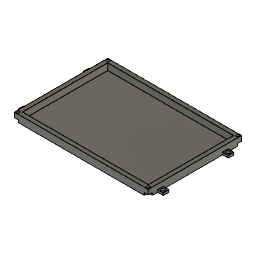
Mainboard frame (Autodesk Fusion 360 design; units mm, degrees)
Autodesk Fusion 360 part; units mm, degrees
sketch "Sketch1" plane through (0, 0, 0) normal (0, 0, 1) x (1, 0, 0)
  line L0 (0, 0) -> (165, 0)
  line L1 (165, 0) -> (165, 115)
  line L2 (165, 115) -> (0, 115)
  line L3 (0, 115) -> (0, 0)
  dimension "d1" = 165
  dimension "d2" = 115
  constraint horizontal L0
  constraint vertical L1
  constraint horizontal L2
  constraint vertical L3
  constraint coincident L0.start L3.end
  measures "d1" distance of L0.start L0.end
  measures "d2" distance of L0.start L2.end
extrude "Extrude1" add sketch "Sketch1" along normal blind 0.8 makes body 1
sketch "Sketch2" plane through (0, 0, 0.8) normal (0, 0, 1) x (-1, 0, 0)
  line L0 (0, -115) -> (0, 0)
  line L1 (0, 0) -> (-165, 0)
  line L2 (-165, 0) -> (-165, -115)
  line L3 (-165, -115) -> (0, -115)
  line L4 (-160, -5) -> (-5, -5)
  line L5 (-5, -5) -> (-5, -110)
  line L6 (-5, -110) -> (-160, -110)
  line L7 (-160, -110) -> (-160, -5)
  line L8 (-160, -5) -> (-5, -110) construction
  line L9 (-5, -5) -> (-160, -110) construction
  point P0 (-82.5, -57.5)
  dimension "d5" = 155
  dimension "d6" = 105
  constraint horizontal L4
  constraint perpendicular L4 L5
  constraint parallel L4 L6
  constraint parallel L5 L7
  constraint coincident L8 P0
  constraint coincident L9 P0
  measures "d5" distance of L5.end L6.end
  measures "d6" distance of L4.end L5.end
extrude "Extrude2" add sketch "Sketch2" along normal blind 0.2 bodies 1
sketch "Sketch3" plane through (0, 0, 1) normal (0, 0, 1) x (-1, 0, 0)
  line L0 (-5, -110) -> (-160, -110)
  line L1 (-160, -110) -> (-160, -5)
  line L2 (-160, -5) -> (-5, -5)
  line L3 (-5, -5) -> (-5, -110)
  line L4 (-165, -115) -> (0, -115)
  line L5 (0, -115) -> (0, 0)
  line L6 (0, 0) -> (-165, 0)
  line L7 (-165, 0) -> (-165, -115)
  circle A0 centre (-2.5, -2.5) radius 1.7
  circle A1 centre (-162.5, -112.5) radius 1.7
  circle A2 centre (-2.5, -112.5) radius 1.7
  circle A3 centre (-162.5, -2.5) radius 1.7
  dimension "d9" = 3.4
  dimension "d10" = 3.4
  dimension "d11" = 3.4
  dimension "d12" = 3.4
  measures "d9" diameter of A0
  measures "d10" diameter of A1
  measures "d11" diameter of A2
  measures "d12" diameter of A3
extrude "Extrude3" cut sketch "Sketch3" against normal blind 367 contours A0 | A1 | A2 | A3 bodies 1
sketch "Sketch4" plane through (0, 0, 0) normal (0, 0, -1) x (1, 0, 0)
  circle A0 centre (162.5, -112.5) radius 1.7
  circle A1 centre (2.5, -2.5) radius 1.7
  circle A2 centre (2.5, -112.5) radius 1.7
  circle A3 centre (162.5, -2.5) radius 1.7
  line L0 (0, 0) -> (0, -115)
  line L1 (0, -115) -> (165, -115)
  line L2 (165, -115) -> (165, 0)
  line L3 (165, 0) -> (0, 0)
sketch "Sketch5" plane through (0, 0, 0) normal (0, 0, -1) x (1, 0, 0)
extrude "Extrude4" add 1 faces at (56.6478, 111.9912, 1) along direction (0, 0, 1) blind 8 on bodies 1 bodies 1
sketch "Sketch6" plane through (0, 0, 0) normal (0, 0, -1) x (1, 0, 0)
  line L0 (5, -5) -> (0, -5)
  line L1 (0, -5) -> (0, 0)
  line L2 (0, 0) -> (5, 0)
  line L3 (5, 0) -> (5, -5)
  line L4 (5, -110) -> (0, -110)
  line L5 (0, -110) -> (0, -115)
  line L6 (0, -115) -> (5, -115)
  line L7 (5, -115) -> (5, -110)
  line L8 (160, -5) -> (165, -5)
  line L9 (165, -5) -> (165, 0)
  line L10 (165, 0) -> (160, 0)
  line L11 (160, 0) -> (160, -5)
  line L12 (160, -110) -> (165, -110)
  line L13 (165, -110) -> (165, -115)
  line L14 (165, -115) -> (160, -115)
  line L15 (160, -115) -> (160, -110)
  constraint horizontal L0
  constraint vertical L1
  constraint horizontal L2
  constraint vertical L3
  constraint coincident L1.end L2.start
  constraint horizontal L4
  constraint vertical L5
  constraint horizontal L6
  constraint vertical L7
  constraint horizontal L8
  constraint vertical L9
  constraint horizontal L10
  constraint vertical L11
  constraint horizontal L12
  constraint vertical L13
  constraint horizontal L14
  constraint vertical L15
extrude "Extrude5" cut sketch "Sketch6" against normal blind 3 bodies 1
sketch "Sketch7" plane through (0, 0, 0) normal (-1, 0, 0) x (0, -1, 0)
  line L0 (-110, 3) -> (-110, 0)
  line L1 (-110, 0) -> (-5, 0)
  line L2 (-5, 0) -> (-5, 3)
  line L3 (-5, 3) -> (0, 3)
  line L4 (0, 3) -> (0, 9)
  line L5 (0, 9) -> (-115, 9)
  line L6 (-115, 9) -> (-115, 3)
  line L7 (-115, 3) -> (-110, 3)
  line L8 (-110, 3) -> (-5, 3)
  line L9 (-55, 1.5) -> (-15, 1.5)
  line L10 (-15, 1.5) -> (-95, 1.5)
  line L11 (-91.5, 0) -> (-98.5, 0)
  line L12 (-98.5, 0) -> (-98.5, 3)
  line L13 (-98.5, 3) -> (-91.5, 3)
  line L14 (-91.5, 3) -> (-91.5, 0)
  line L15 (-91.5, 0) -> (-98.5, 3) construction
  line L16 (-98.5, 0) -> (-91.5, 3) construction
  line L17 (-11.5, 0) -> (-18.5, 0)
  line L18 (-18.5, 0) -> (-18.5, 3)
  line L19 (-18.5, 3) -> (-11.5, 3)
  line L20 (-11.5, 3) -> (-11.5, 0)
  line L21 (-11.5, 0) -> (-18.5, 3) construction
  line L22 (-18.5, 0) -> (-11.5, 3) construction
  point P0 (-95, 1.5)
  point P1 (-15, 1.5)
  dimension "d24" = 7
  dimension "d25" = 7
  dimension "d26" = 3
  constraint coincident L0.start L7.end
  constraint coincident L2.end L3.start
  constraint parallel L1 L9
  constraint parallel L1 L10
  constraint horizontal L11
  constraint perpendicular L11 L12
  constraint parallel L11 L13
  constraint parallel L12 L14
  constraint coincident L15 P0
  constraint coincident L16 P0
  constraint coincident P0 L10.end
  constraint horizontal L17
  constraint perpendicular L17 L18
  constraint parallel L17 L19
  constraint parallel L18 L20
  constraint coincident L21 P1
  constraint coincident L22 P1
  constraint coincident P1 L9.end
  measures "d24" distance of L12.end L13.end
  measures "d25" distance of L18.end L19.end
  measures "d26" distance of L17.end L18.end
extrude "Extrude6" add sketch "Sketch7" along normal blind 7 separate body contours L1 L8 L11 L12 L13 L14 | L1 L8 L17 L18 L19 L20 makes body 2 at (-2.3333, 96.1667, 3) makes body 3 at (-4.6667, 13.8333, 3)
extrude "Extrude7" add 2 faces at (-7, 96.1667, 2) (-7, 13.8333, 2) along direction (1, 0, 0) blind 179 on bodies 2 3 bodies 1 2 3
extrude "Extrude8" cut 2 faces at (56.6667, 16.1667, 3) (56.6667, 96.1667, 3) along direction (0, 0, -1) blind 2.2 on bodies 1 bodies 1
sketch "Sketch8" plane through (0, 0, 3) normal (0, 0, 1) x (-1, 0, 0)
  line L0 (-165, -18.5) -> (-165, -11.5)
  line L1 (-165, -11.5) -> (-172, -11.5)
  line L2 (-172, -11.5) -> (-172, -18.5)
  line L3 (-172, -18.5) -> (-165, -18.5)
  circle A0 centre (-168.5, -15) radius 2.15
  circle A1 centre (-168.5, -95) radius 2.15
  circle A2 centre (3.5, -95) radius 2.15
  circle A3 centre (3.5, -15) radius 2.1
  dimension "d33" = 4.3
  dimension "d34" = 4.3
  dimension "d35" = 4.3
  dimension "d36" = 4.2
  measures "d33" diameter of A0
  measures "d34" diameter of A1
  measures "d35" diameter of A2
  measures "d36" diameter of A3
extrude "Extrude9" cut sketch "Sketch8" against normal blind 36 contours A0 | A1 | A2 | A3 bodies 1
equation "d29 = -7 mm - 165 mm - 7.00 mm"
